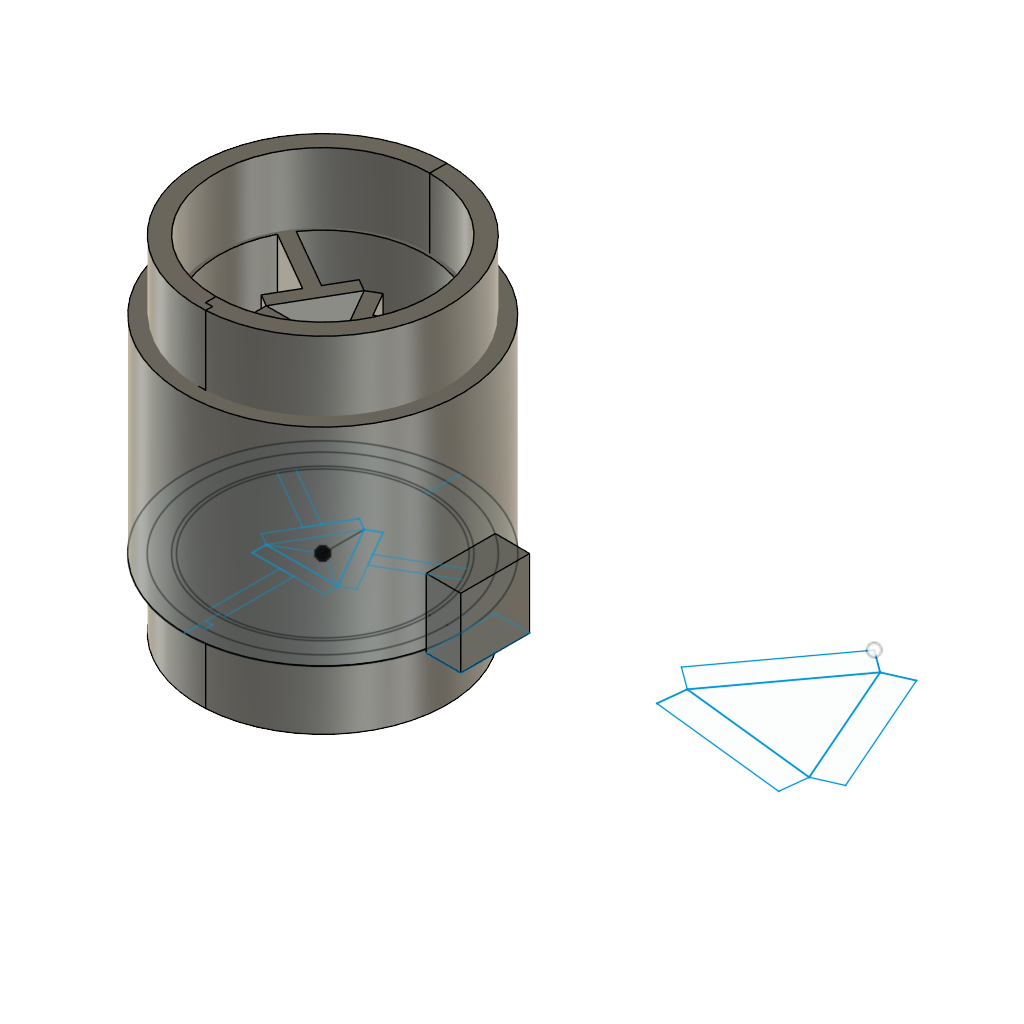
piston-v2 (Autodesk Fusion 360 design; units mm, degrees)
part number: 2026-11-23-15-58-47-754
Autodesk Fusion 360 part; units mm, degrees
sketch "草图1" plane through (0, 0, 0) normal (0, 0, 1) x (1, 0, 0)
  circle A0 centre (0, 0) radius 75
  circle A1 centre (0, 0) radius 100
  line L0 (0, -75) -> (0, -85)
  line L1 (0, -85) -> (5, -85)
  line L2 (5, -85) -> (5, -90)
  line L3 (5, -90) -> (0, -90)
  line L4 (0, -90) -> (0, -100)
  line L5 (0, 100) -> (0, 75)
  line L6 (276.6423, 127.379) -> (217.3979, 46.8178)
  line L7 (217.3979, 46.8178) -> (316.7881, 35.7913)
  line L8 (316.7881, 35.7913) -> (276.6423, 127.379)
  line L9 (276.6423, 127.379) -> (260.53, 139.2278)
  line L10 (276.6423, 127.379) -> (294.9598, 135.4081)
  line L11 (217.3979, 46.8178) -> (215.1926, 26.9397)
  line L12 (217.3979, 46.8178) -> (276.6423, 127.379)
  line L13 (276.6423, 127.379) -> (260.53, 139.2278)
  line L14 (260.53, 139.2278) -> (201.2857, 58.6666)
  line L15 (201.2857, 58.6666) -> (217.3979, 46.8178)
  line L16 (276.6423, 127.379) -> (294.9598, 135.4081)
  line L17 (294.9598, 135.4081) -> (335.1057, 43.8204)
  line L18 (335.1057, 43.8204) -> (316.7881, 35.7913)
  line L19 (316.7881, 35.7913) -> (276.6423, 127.379)
  line L20 (217.3979, 46.8178) -> (215.1926, 26.9397)
  line L21 (215.1926, 26.9397) -> (314.5828, 15.9132)
  line L22 (314.5828, 15.9132) -> (316.7881, 35.7913)
  line L23 (316.7881, 35.7913) -> (217.3979, 46.8178)
  line L24 (0, 0) -> (0, 30)
  line L25 (0, 0) -> (-25.9808, -15)
  line L26 (0, 0) -> (25.9808, -15)
  line L27 (-25.9808, -15) -> (25.9808, -15)
  line L28 (0, 30) -> (25.9808, -15)
  line L29 (0, 30) -> (8.6603, 35)
  line L30 (0, 30) -> (-8.6603, 35)
  line L31 (-25.9808, -15) -> (-25.9808, -25)
  line L32 (-25.9808, -15) -> (0, 30)
  line L33 (0, 30) -> (-8.6603, 35)
  line L34 (-8.6603, 35) -> (-34.641, -10)
  line L35 (-34.641, -10) -> (-25.9808, -15)
  line L36 (-25.9808, -25) -> (25.9808, -25)
  line L37 (25.9808, -25) -> (25.9808, -15)
  line L38 (25.9808, -15) -> (-25.9808, -15)
  line L39 (-25.9808, -15) -> (-25.9808, -25)
  line L40 (8.6603, 35) -> (0, 30)
  line L41 (0, 30) -> (25.9808, -15)
  line L42 (25.9808, -15) -> (34.641, -10)
  line L43 (34.641, -10) -> (8.6603, 35)
  line L44 (8.6603, 35) -> (18.6603, 17.6795)
  line L45 (18.6603, 17.6795) -> (23.6603, 9.0192)
  line L46 (18.6603, 17.6795) -> (61.7547, 42.5601)
  line L47 (23.6603, 9.0192) -> (66.8682, 33.9654)
  line L48 (-25.9808, -25) -> (-5.9808, -25)
  line L49 (-5.9808, -25) -> (4.0192, -25)
  line L50 (-5.9808, -25) -> (-5.9808, -74.7612)
  line L51 (4.0192, -25) -> (4.0192, -74.8922)
  line L52 (-8.6603, 35) -> (-18.6603, 17.6795)
  line L53 (-18.6603, 17.6795) -> (-23.6603, 9.0192)
  line L54 (-18.6603, 17.6795) -> (-61.7547, 42.5601)
  line L55 (-23.6603, 9.0192) -> (-66.8682, 33.9654)
  circle A2 centre (0, 0) radius 77.5
  circle A3 centre (0, 0) radius 90
  line L56 (100, 25) -> (125, 25)
  line L57 (125, 25) -> (125, -25)
  line L58 (125, -25) -> (100, -25)
  line L59 (100, -25) -> (100, 25)
  dimension "d1" = 150
  dimension "d2" = 200
  dimension "d3" = 60
  dimension "d4" = 60
  dimension "d5" = 100
  dimension "d6" = 20
  dimension "d7" = 90
  dimension "d8" = 20
  dimension "d9" = 20
  dimension "d38" = 10
  dimension "d61" = 155
  dimension "d62" = 180
  constraint coincident A0.centre A1.centre
  constraint coincident A0 L0.start
  constraint perpendicular A0 L0
  constraint perpendicular L0 L1
  constraint perpendicular L1 L2
  constraint perpendicular L2 L3
  constraint coincident A1 L4.end
  constraint perpendicular A1 L4
  constraint coincident A1 L5.start
  constraint coincident A0 L5.end
  constraint perpendicular A0 L5
  constraint perpendicular L6 L9
  constraint perpendicular L7 L11
  constraint perpendicular L12 L13
  constraint parallel L12 L14
  constraint parallel L13 L15
  constraint perpendicular L16 L17
  constraint parallel L16 L18
  constraint parallel L17 L19
  constraint perpendicular L20 L21
  constraint parallel L20 L22
  constraint parallel L21 L23
  constraint vertical L24
  constraint horizontal L27
  constraint perpendicular L28 L29
  constraint perpendicular L32 L33
  constraint parallel L32 L34
  constraint parallel L33 L35
  constraint horizontal L36
  constraint vertical L37
  constraint horizontal L38
  constraint vertical L39
  constraint perpendicular L40 L41
  constraint parallel L40 L42
  constraint parallel L41 L43
  constraint perpendicular L29 L44
  constraint parallel L43 L45
  constraint coincident A0 L46.end
  constraint perpendicular L45 L46
  constraint coincident A0 L47.end
  constraint perpendicular L45 L47
  constraint perpendicular L31 L48
  constraint parallel L36 L49
  constraint coincident A0 L50.end
  constraint perpendicular L49 L50
  constraint coincident A0 L51.end
  constraint perpendicular L49 L51
  constraint perpendicular L33 L52
  constraint parallel L34 L53
  constraint coincident A0 L54.end
  constraint perpendicular L34 L54
  constraint coincident A0 L55.end
  constraint perpendicular L34 L55
  constraint concentric A1 A3
  constraint horizontal L56
  constraint vertical L57
  constraint horizontal L58
  constraint vertical L59
  measures "d1" diameter of A0
  measures "d2" diameter of A1
  measures "d3" angle of L6 L8
  measures "d4" angle of L6 L7
  measures "d5" distance of L6.start L6.end
  measures "d6" distance of L6.start L9.end
  measures "d7" angle of L8 L10
  measures "d8" distance of L6.start L10.end
  measures "d9" distance of L6.end L11.end
  measures "d38" distance of L48.end L49.end
  measures "d61" diameter of A2
  measures "d62" diameter of A3
extrude "拉伸9" add sketch "草图1" along normal blind 200 and the other way blind 50 contours L0 L1 L2 L5 A2 A3 picked at (-8.3215, -83.5431) makes body 1
extrude "拉伸10" add sketch "草图1" along normal blind 200 and the other way blind 50 separate body contours L0 L1 L2 L5 A2 A3 picked at (22.7938, -82.5988) makes body 2
extrude "拉伸11" add sketch "草图1" along normal blind 150 separate body contours A0 L0 L5 A2 | L0 L1 L2 L5 A2 A3 | A1 L4 L5 A3 picked at (-11.2971, -74.8632) picked at (-8.3215, -83.5431) makes body 3
extrude "拉伸12" add sketch "草图1" along normal blind 150 separate body contours A0 L0 L5 A2 | L0 L1 L2 L5 A2 A3 | A1 L2 L3 L4 L5 A3 picked at (9.7755, -75.0773) picked at (22.7938, -82.5988) makes body 4
extrude "拉伸13" add sketch "草图1" along normal blind 150 separate body contours L28 L29 L40 L41 L42 L43 L44 L45 | L27 L31 L36 L37 L38 L39 L48 L49 | L30 L32 L33 L34 L35 L52 L53 makes body 5
extrude "拉伸14" add sketch "草图1" along normal blind 150 contours A0 L43 L45 L46 L47 | A0 L36 L49 L50 L51 | A0 L34 L53 L54 L55 bodies 3 4 5
extrude "拉伸15" add sketch "草图1" along normal blind 50 separate body contours L56 L57 L58 L59 makes body 6
